Autodesk Fusion 360 part; units mm, degrees
(part 2 of 2)
sketch "Sketch8" plane through (0, 0, 0) normal (-1, 0, 0) x (0, -1, 0)
  circle A0 centre (117.475, 1.5875) radius 2.1
  line L0 (65.405, -4.7625) -> (65.405, -1.5875)
  line L1 (65.405, -1.5875) -> (133.35, -1.5875)
  line L2 (133.35, -1.5875) -> (133.35, 4.7625)
  line L3 (133.35, 4.7625) -> (-31.75, 4.7625)
  line L4 (-31.75, 4.7625) -> (-31.75, -4.7625)
  line L5 (-31.75, -4.7625) -> (65.405, -4.7625)
  circle A1 centre (117.475, 11.4427) radius 2.1
  circle A2 centre (117.475, 11.4427) radius 3.175
  circle A3 centre (106.045, 11.4427) radius 2.1
  circle A4 centre (106.045, 11.4427) radius 3.175
  line L6 (117.475, 8.2677) -> (106.045, 8.2677)
  line L7 (117.475, 14.6177) -> (106.045, 14.6177)
  line L8 (106.045, 14.6177) -> (70.9402, 14.6177)
  line L9 (70.9402, 14.6177) -> (65.405, 6.5046)
  line L10 (106.045, 8.2677) -> (74.295, 8.2677)
  line L11 (74.295, 8.2677) -> (65.405, -4.7625)
  line L12 (65.405, 6.5046) -> (65.405, -4.7625)
  line L13 (65.405, 6.5046) -> (64.2164, 4.7625)
  line L14 (120.65, 8.2677) -> (102.87, 8.2677)
  line L15 (102.87, 8.2677) -> (102.87, 14.6177)
  line L16 (102.87, 14.6177) -> (120.65, 14.6177)
  line L17 (120.65, 14.6177) -> (120.65, 8.2677)
  dimension "d38" = 4.2
  dimension "d39" = 9.8552
  dimension "d40" = 6.35
  dimension "d45" = 4.2
  dimension "d46" = 6.35
  dimension "d47" = 11.43
  dimension "d66" = 6.35
  dimension "d68" = 31.75
  dimension "d69" = 6.35
  constraint vertical A0.centre A1.centre
  constraint concentric A1 A2
  constraint concentric A3 A4
  constraint horizontal A1.centre A3.centre
  constraint coincident A2 L6.start
  constraint coincident A4 L6.end
  constraint coincident A2 L7.start
  constraint coincident A4 L7.end
  constraint tangent A4 L7
  constraint horizontal L6
  constraint horizontal L7
  constraint parallel L7 L8
  constraint parallel L3 L10
  constraint coincident L0.start L5.end
  constraint parallel L9 L11
  constraint vertical L9.end L0.start
  constraint coincident L3 L13.end
  constraint parallel L9 L13
  constraint horizontal L14
  constraint vertical L15
  constraint horizontal L16
  constraint vertical L17
  constraint coincident L8 L15.end
  constraint coincident L10 L14.end
  constraint tangent A2 L17
  constraint tangent A4 L15
  measures "d38" diameter of A1
  measures "d39" vertical distance of A0.centre A1.centre
  measures "d40" diameter of A2
  measures "d45" diameter of A3
  measures "d46" diameter of A4
  measures "d47" distance of A1.centre A3.centre
  measures "d66" distance of L8 L10
  measures "d68" distance of L6.end L10.end
  measures "d69" distance of L9 L11
extrude "Extrude7" cut sketch "Sketch8" against normal blind 6.35 contours L0 L1 L11 L12 | L1 L2 L3 L11
extrude "Extrude8" add sketch "Sketch8" along normal blind -6.35 and the other way blind 2.54 contours L0 L1 L11 L12 | L1 L3 L11 L12 | L3 L8 L9 L10 L11 L12 L15 | L3 L12 L13 | A4 L10 L14 L15 | A4 L8 L15 L16 | A4 | A2 A4 L6 L7 L14 L16 | A2 | A2 L14 L17 | A2 L16 L17 | A1 | A3
extrude "Extrude9" add sketch "Sketch8" against normal blind 2.54 contours L0 L1 L11 L12 | A4 L10 L14 L15 | A4 L8 L15 L16 | A4 | A2 A4 L6 L7 L14 L16 | A2 | A2 L14 L17 | A2 L16 L17 | A1 | A3
sketch "Sketch10" plane through (0, 0, -4.7625) normal (0, 0, -1) x (1, 0, 0)
  line L0 (6.35, 65.405) -> (0, 65.405)
  line L1 (0, 65.405) -> (0, -31.75)
  line L2 (0, -31.75) -> (6.35, -31.75)
  line L3 (6.35, -31.75) -> (6.35, 65.405)
  line L4 (6.35, -31.75) -> (0, -31.75)
  line L5 (0, -31.75) -> (0, 65.405)
  line L6 (0, 65.405) -> (6.35, 65.405)
  line L7 (6.35, 65.405) -> (6.35, -31.75)
  constraint horizontal L4
  constraint vertical L5
  constraint horizontal L6
  constraint vertical L7
  constraint coincident L0.end L1.start
  constraint coincident L2.end L3.start
extrude "Extrude12" add sketch "Sketch10" along normal blind 0.4318
sketch "Sketch9" plane through (6.35, 0, 0) normal (1, 0, 0) x (0, 1, 0)
  circle A0 centre (25.4, 0) radius 2.1971
  circle A1 centre (0, 0) radius 2.1971
  circle A2 centre (-12.7, 1.5875) radius 1.6
  circle A3 centre (-63.5, 1.5875) radius 1.6
  line L0 (-90.805, 4.7625) -> (-90.805, -4.7625)
  line L1 (-90.805, -4.7625) -> (31.75, -4.7625)
  line L2 (31.75, -4.7625) -> (31.75, 4.7625)
  line L3 (31.75, 4.7625) -> (-90.805, 4.7625)
  line L4 (17.4625, -1.5875) -> (17.4625, -4.7625)
  line L5 (17.4625, -4.7625) -> (7.9375, -4.7625)
  line L6 (7.9375, -4.7625) -> (7.9375, -1.5875)
  line L7 (7.9375, -1.5875) -> (17.4625, -1.5875)
  line L8 (0, -2.1971) -> (7.9375, -2.1971)
  dimension "d55" = 9.525
  dimension "d56" = 3.175
  dimension "d57" = 7.9375
  constraint vertical L4
  constraint horizontal L5
  constraint vertical L6
  constraint perpendicular L4 L7
  constraint collinear L1 L5
  constraint coincident A1 L8.start
  constraint coincident L6 L8.end
  constraint tangent A1 L8
  constraint perpendicular L6 L8
  measures "d55" distance of L6.end L4.start
  measures "d56" distance of L4.end L4.start
  measures "d57" distance of L8.start L8.end
extrude "Extrude10" [suppressed]
extrude "Extrude11" [suppressed]
equation "d7 = 0.5 in - ( 0.2 / 2 ) * 1 in"
equation "d10 = ( 0.375 / 2 ) * 1 in"
equation "d11 = ( ( 1.5 - 1 ) / 2 ) * 1 in"
equation "d39 = 0.263 in + 0.125 in"

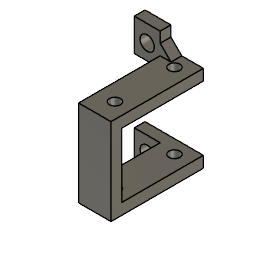
design "Yellow Motor Mount"
Autodesk Fusion 360 part; units mm, degrees
sketch "Sketch1" plane through (0, 0, 0) normal (0, 0, 1) x (1, 0, 0)
  line L0 (0, 0) -> (9.525, 0)
  line L1 (9.525, 0) -> (9.525, 27.1272)
  line L2 (9.525, 27.1272) -> (0, 27.1272)
  line L3 (0, 27.1272) -> (0, 0)
  circle A0 centre (5.0144, 5.675) radius 1.6
  circle A1 centre (5.0144, 23.1329) radius 1.6
  dimension "d1" = 3.2
  dimension "d2" = 3.2
  dimension "d3" = 17.4579
  dimension "d4" = 5.0144
  dimension "d5" = 5.675
  dimension "d6" = 9.525
  dimension "d7" = 27.1272
  constraint horizontal L0
  constraint vertical L1
  constraint horizontal L2
  constraint vertical L3
  constraint coincident L0.start L3.end
  constraint vertical A0.centre A1.centre
  measures "d1" diameter of A1
  measures "d2" diameter of A0
  measures "d3" distance of A0.centre A1.centre
  measures "d4" distance of L3 A1.centre
  measures "d5" distance of L0 A0.centre
  measures "d6" distance of L1 L3
  measures "d7" distance of L0 L2
extrude "Extrude1" add sketch "Sketch1" along normal blind 25.4
sketch "Sketch2" plane through (0, 0, 0) normal (-1, 0, 0) x (0, -1, 0)
  line L0 (-27.1272, 0) -> (0, 0)
  line L1 (0, 0) -> (0, 25.4)
  line L2 (0, 25.4) -> (-27.1272, 25.4)
  line L3 (-27.1272, 25.4) -> (-27.1272, 0)
  line L4 (-3.175, 3.302) -> (-27.1272, 3.302)
  line L5 (-27.1272, 3.302) -> (-27.1272, 22.1488)
  line L6 (-27.1272, 22.1488) -> (-3.175, 22.1488)
  line L7 (-3.175, 22.1488) -> (-3.175, 3.302)
  line L8 (-24.5872, 25.4) -> (-27.1272, 25.4)
  line L9 (-27.1272, 25.4) -> (-27.1272, 34.925)
  line L10 (-27.1272, 34.925) -> (-24.5872, 34.925)
  line L11 (-24.5872, 34.925) -> (-24.5872, 25.4)
  line L12 (-27.1272, 0) -> (-24.5872, 0)
  line L13 (-24.5872, 0) -> (-24.5872, -9.525)
  line L14 (-24.5872, -9.525) -> (-27.1272, -9.525)
  line L15 (-27.1272, -9.525) -> (-27.1272, 0)
  dimension "d11" = 3.302
  dimension "d12" = 18.8468
  dimension "d16" = 3.175
  dimension "d17" = 2.54
  dimension "d18" = 2.54
  dimension "d19" = 9.525
  dimension "d20" = 9.525
  constraint horizontal L4
  constraint vertical L5
  constraint horizontal L6
  constraint vertical L7
  constraint coincident L3 L5.end
  constraint horizontal L8
  constraint vertical L9
  constraint horizontal L10
  constraint vertical L11
  constraint coincident L2 L8.start
  constraint horizontal L12
  constraint vertical L13
  constraint horizontal L14
  constraint vertical L15
  constraint coincident L0.start L3.end
  constraint coincident L2.end L3.start
  measures "d11" distance of L0 L4
  measures "d12" distance of L4 L6
  measures "d16" distance of L1 L7
  measures "d17" distance of L9 L11
  measures "d18" distance of L13 L15
  measures "d19" distance of L8.start L10.end
  measures "d20" distance of L12.end L13.end
extrude "Extrude2" cut sketch "Sketch2" against normal blind 9.525 contours L3 L4 L5 L6 L7
sketch "Sketch3" plane through (0, 0, 0) normal (-1, 0, 0) x (0, -1, 0)
  line L0 (-3.175, 22.1488) -> (-3.175, 3.302)
  line L1 (-3.175, 3.302) -> (-27.1272, 3.302)
  line L2 (-27.1272, 3.302) -> (-27.1272, 0)
  line L3 (-27.1272, 0) -> (0, 0)
  line L4 (0, 0) -> (0, 25.4)
  line L5 (-27.1272, 3.302) -> (-23.9522, 3.302)
  line L6 (-23.9522, 3.302) -> (-23.9522, -6.223)
  line L7 (-23.9522, -6.223) -> (-27.1272, -6.223)
  line L8 (-27.1272, -6.223) -> (-27.1272, 3.302)
  line L9 (-27.1272, 22.1488) -> (-23.9522, 22.1488)
  line L10 (-23.9522, 22.1488) -> (-23.9522, 31.6738)
  line L11 (-23.9522, 31.6738) -> (-27.1272, 31.6738)
  line L12 (-27.1272, 31.6738) -> (-27.1272, 22.1488)
  point P0 (-27.1272, 22.1488)
  dimension "d23" = 3.175
  dimension "d24" = 9.525
  dimension "d26" = 9.525
  dimension "d27" = 3.175
  constraint horizontal L5
  constraint vertical L6
  constraint horizontal L7
  constraint vertical L8
  constraint coincident L1.end L2.start
  constraint horizontal L9
  constraint vertical L10
  constraint horizontal L11
  constraint vertical L12
  constraint coincident P0 L9.start
  measures "d23" distance of L6.end L7.end
  measures "d24" distance of L1.end L7.end
  measures "d26" distance of P0 L11.end
  measures "d27" distance of P0 L9.end
extrude "Extrude4" add sketch "Sketch3" along normal blind 7.62
chamfer "Chamfer1" distance 3.175 angle 45 2 edges at (0, 25.5397, 25.4) (0, 25.5397, 0)
sketch "Sketch4" plane through (0, 27.1272, 0) normal (0, 1, 0) x (-1, 0, 0)
  line L0 (-9.525, 22.1488) -> (7.62, 22.1488)
  line L1 (7.62, 22.1488) -> (7.62, 31.6738)
  line L2 (7.62, 31.6738) -> (0, 31.6738)
  line L3 (0, 31.6738) -> (0, 28.575)
  line L4 (0, 28.575) -> (-3.175, 25.4)
  line L5 (-3.175, 25.4) -> (-9.525, 25.4)
  line L6 (-9.525, 25.4) -> (-9.525, 22.1488)
  circle A0 centre (3.81, 26.7254) radius 2.1
  circle A1 centre (3.81, -1.2746) radius 2.1
  line L7 (3.81, 26.7254) -> (3.81, 31.6738)
  line L8 (3.81, -1.2746) -> (3.81, -6.223)
  line L9 (0, -6.223) -> (7.62, -6.223)
  dimension "d31" = 4.2
  dimension "d32" = 4.2
  dimension "d33" = 28
  dimension "d34" = 3.81
  constraint vertical A0.centre A1.centre
  constraint coincident A0.centre L7.start
  constraint midpoint L2 L7.end
  constraint coincident A1.centre L8.start
  constraint vertical L8
  constraint equal L7 L8
  constraint coincident L8.end L9
  measures "d31" diameter of A1
  measures "d32" diameter of A0
  measures "d33" distance of A0.centre A1.centre
  measures "d34" distance of L1 A0.centre
extrude "Extrude5" cut sketch "Sketch4" against normal blind 3.175 contours A0 | A1
equation "d5 = 2.5 mm + 0.125 in"
equation "d6 = ( 3 / 8 ) * 1 in"
equation "d7 = 0.943 in + 0.125 in"
equation "d11 = ( 1 - 0.74 ) / 2 * 1 in"
equation "d19 = ( 3 / 8 ) * 1 in"
equation "d20 = ( 3 / 8 ) * 1 in"
equation "d24 = ( 3 / 8 ) * 1 in"
equation "d26 = ( 3 / 8 ) * 1 in"

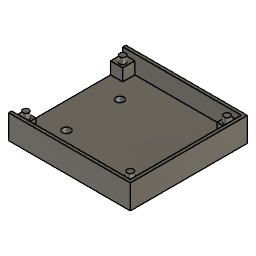
design "Controller Mounting"
Autodesk Fusion 360 part; units mm, degrees
sketch "Sketch1" plane through (0, 0, 0) normal (0, 0, 1) x (1, 0, 0)
  line L0 (0, 0) -> (65.175, 0)
  line L1 (65.175, 0) -> (65.175, 61.175)
  line L2 (65.175, 61.175) -> (0, 61.175)
  line L3 (0, 61.175) -> (0, 0)
  dimension "d1" = 61.175
  dimension "d2" = 65.175
  constraint horizontal L0
  constraint vertical L1
  constraint horizontal L2
  constraint vertical L3
  constraint coincident L0.start L3.end
  measures "d1" distance of L0.start L2.end
  measures "d2" distance of L0.start L0.end
extrude "Extrude1" add sketch "Sketch1" along normal blind 12.7
sketch "Sketch4" plane through (0, 0, 12.7) normal (0, 0, 1) x (-1, 0, 0)
  line L0 (0, -61.175) -> (0, 0)
  line L1 (0, 0) -> (-65.175, 0)
  line L2 (-65.175, 0) -> (-65.175, -61.175)
  line L3 (-65.175, -61.175) -> (0, -61.175)
  line L4 (-1.5875, -1.5875) -> (-63.5875, -1.5875)
  line L5 (-63.5875, -1.5875) -> (-63.5875, -59.5875)
  line L6 (-63.5875, -59.5875) -> (-1.5875, -59.5875)
  line L7 (-1.5875, -59.5875) -> (-1.5875, -1.5875)
  dimension "d10" = 1.5875
  dimension "d11" = 1.5875
  dimension "d12" = 1.5875
  dimension "d13" = 1.5875
  constraint horizontal L4
  constraint vertical L5
  constraint horizontal L6
  constraint vertical L7
  measures "d10" distance of L0 L7
  measures "d11" distance of L3 L6
  measures "d12" distance of L1 L4
  measures "d13" distance of L2 L5
extrude "Extrude2" cut sketch "Sketch4" against normal blind 9.525 contours L4 L5 L6 L7
sketch "Sketch5" plane through (0, 0, 0) normal (-1, 0, 0) x (0, -1, 0)
  line L0 (-61.175, 0) -> (0, 0)
  line L1 (0, 0) -> (0, 12.7)
  line L2 (0, 12.7) -> (-61.175, 12.7)
  line L3 (-61.175, 12.7) -> (-61.175, 0)
  line L4 (-53.2375, 12.7) -> (-7.9375, 12.7)
  line L5 (-7.9375, 12.7) -> (-7.9375, 0)
  line L6 (-53.2375, 0) -> (-53.2375, 12.7)
  line L7 (-53.2375, 3.175) -> (-59.5875, 3.175)
  line L8 (-59.5875, 3.175) -> (-59.5875, 12.7)
  line L9 (-59.5875, 12.7) -> (-53.2375, 12.7)
  line L10 (-53.2375, 12.7) -> (-53.2375, 3.175)
  line L11 (-7.9375, 3.175) -> (-1.5875, 3.175)
  line L12 (-1.5875, 3.175) -> (-1.5875, 12.7)
  line L13 (-1.5875, 12.7) -> (-7.9375, 12.7)
  line L14 (-7.9375, 12.7) -> (-7.9375, 3.175)
  line L15 (-53.2375, 3.175) -> (-7.9375, 3.175)
  dimension "d76" = 1.5875
  dimension "d77" = 3.175
  dimension "d78" = 3.175
  dimension "d79" = 1.5875
  dimension "d80" = 6.35
  dimension "d81" = 6.35
  constraint horizontal L4
  constraint vertical L5
  constraint vertical L6
  constraint coincident L2 L4.start
  constraint horizontal L5.end L6.start
  constraint horizontal L0.end L6.start
  constraint horizontal L7
  constraint vertical L8
  constraint horizontal L9
  constraint vertical L10
  constraint coincident L2 L8.end
  constraint coincident L6 L7.start
  constraint horizontal L11
  constraint vertical L12
  constraint horizontal L13
  constraint vertical L14
  constraint coincident L2 L12.end
  constraint coincident L5 L11.start
  measures "d76" distance of L3 L8
  measures "d77" distance of L0 L7
  measures "d78" distance of L0 L11
  measures "d79" distance of L1 L12
  measures "d80" distance of L8 L10
  measures "d81" distance of L12 L14
extrude "Extrude3" cut sketch "Sketch5" against normal blind 1.5875
sketch "Sketch6" plane through (0, 0, 3.175) normal (0, 0, 1) x (-1, 0, 0)
  circle A0 centre (-59.8375, -5.3375) radius 1.65
  circle A1 centre (-5.3375, -5.3375) radius 1.65
  circle A2 centre (-59.8375, -55.8375) radius 1.65
  circle A3 centre (-5.3375, -55.8375) radius 1.65
  line L0 (-63.5875, -1.5875) -> (-57.2375, -1.5875)
  line L1 (-57.2375, -1.5875) -> (-57.2375, -7.9375)
  line L2 (-57.2375, -7.9375) -> (-63.5875, -7.9375)
  line L3 (-63.5875, -7.9375) -> (-63.5875, -1.5875)
  line L4 (-63.5875, -59.5875) -> (-57.2375, -59.5875)
  line L5 (-57.2375, -59.5875) -> (-57.2375, -53.2375)
  line L6 (-57.2375, -53.2375) -> (-63.5875, -53.2375)
  line L7 (-63.5875, -53.2375) -> (-63.5875, -59.5875)
  line L8 (-1.5875, -59.5875) -> (-7.9375, -59.5875)
  line L9 (-7.9375, -59.5875) -> (-7.9375, -53.2375)
  line L10 (-7.9375, -53.2375) -> (-1.5875, -53.2375)
  line L11 (-1.5875, -53.2375) -> (-1.5875, -59.5875)
  line L12 (-1.5875, -1.5875) -> (-7.9375, -1.5875)
  line L13 (-7.9375, -1.5875) -> (-7.9375, -7.9375)
  line L14 (-7.9375, -7.9375) -> (-1.5875, -7.9375)
  line L15 (-1.5875, -7.9375) -> (-1.5875, -1.5875)
  line L16 (-65.175, 0) -> (-65.175, -61.175)
  line L17 (-65.175, -61.175) -> (0, -61.175)
  line L18 (-1.5875, -1.5875) -> (-63.5875, -1.5875)
  line L19 (-63.5875, -1.5875) -> (-63.5875, -59.5875)
  line L20 (-63.5875, -59.5875) -> (-1.5875, -59.5875)
  line L21 (-1.5875, -59.5875) -> (-1.5875, -1.5875)
  dimension "d82" = 3.3
  dimension "d83" = 50.5
  dimension "d84" = 50.5
  dimension "d85" = 54.5
  dimension "d86" = 3.3
  dimension "d87" = 3.3
  dimension "d88" = 5.3375
  dimension "d89" = 5.3375
  dimension "d90" = 6.35
  dimension "d91" = 6.35
  dimension "d92" = 6.35
  dimension "d93" = 6.35
  dimension "d94" = 6.35
  dimension "d95" = 6.35
  dimension "d96" = 6.35
  dimension "d97" = 6.35
  dimension "d98" = 1.5875
  dimension "d100" = 1.5875
  dimension "d101" = 1.5875
  dimension "d102" = 1.5875
  constraint horizontal A0.centre A1.centre
  constraint horizontal A2.centre A3.centre
  constraint vertical A1.centre A3.centre
  constraint equal A0 A1
  constraint horizontal L0
  constraint vertical L1
  constraint horizontal L2
  constraint vertical L3
  constraint horizontal L4
  constraint vertical L5
  constraint horizontal L6
  constraint vertical L7
  constraint horizontal L8
  constraint vertical L9
  constraint horizontal L10
  constraint vertical L11
  constraint horizontal L12
  constraint vertical L13
  constraint horizontal L14
  constraint vertical L15
  constraint horizontal L1.end L13.end
  constraint vertical L9.end L13.end
  constraint horizontal L5.end L9.end
  constraint vertical L1.end L5.end
  measures "d82" diameter of A0
  measures "d83" distance of A0.centre A2.centre
  measures "d84" vertical distance of A1.centre A3.centre
  measures "d85" distance of A0.centre A1.centre
  measures "d86" diameter of A2
  measures "d87" diameter of A3
  measures "d88" vertical distance of origin A0.centre
  measures "d89" horizontal distance of origin A1.centre
  measures "d90" distance of L12.end L13.end
  measures "d91" distance of L13.end L14.end
  measures "d92" distance of L9.end L10.end
  measures "d93" distance of L8.end L9.end
  measures "d94" distance of L4.end L5.end
  measures "d95" distance of L5.end L6.end
  measures "d96" distance of L1.end L2.end
  measures "d97" distance of L0.end L1.end
  measures "d98" distance of origin L12
  measures "d100" distance of origin L15
  measures "d101" distance of L3 L16
  measures "d102" distance of L4 L17
extrude "Extrude4" add sketch "Sketch6" along normal blind 6.35 contours A0 | A1 | A2 | A3 | L0 L1 L2 L3 L18 L19 | L12 L13 L14 L15 L18 L21 | L4 L5 L6 L7 L19 L20 | L8 L9 L10 L11 L20 L21
extrude "Extrude8" add sketch "Sketch6" along normal blind 9.525 contours A0 | A1 | A2 | A3
sketch "Sketch7" plane through (0, 0, 3.175) normal (0, 0, 1) x (-1, 0, 0)
  line L0 (-7.9375, -1.5875) -> (-57.2375, -1.5875)
  circle A0 centre (-15.2005, -16.6175) radius 2.1
  circle A1 centre (-15.2005, -44.5575) radius 2.1
  line L1 (-1.5875, 0) -> (-65.175, 0)
  line L2 (-15.2005, -16.6175) -> (-15.2005, -44.5575)
  line L3 (-15.2005, 0) -> (-15.2005, -61.175)
  line L4 (-65.175, -61.175) -> (-1.5875, -61.175)
  line L5 (-57.2375, -59.5875) -> (-7.9375, -59.5875)
  line L6 (-63.5875, -7.9375) -> (-63.5875, -53.2375)
  line L7 (-63.5875, -53.2375) -> (-57.2375, -53.2375)
  line L8 (-57.2375, -53.2375) -> (-57.2375, -59.5875)
  line L9 (-7.9375, -59.5875) -> (-7.9375, -53.2375)
  line L10 (-7.9375, -53.2375) -> (-1.5875, -53.2375)
  line L11 (-1.5875, -53.2375) -> (-1.5875, -7.9375)
  line L12 (-1.5875, -7.9375) -> (-7.9375, -7.9375)
  line L13 (-7.9375, -7.9375) -> (-7.9375, -1.5875)
  line L14 (-57.2375, -1.5875) -> (-57.2375, -7.9375)
  line L15 (-57.2375, -7.9375) -> (-63.5875, -7.9375)
  dimension "d41" = 4.2
  dimension "d42" = 4.2
  dimension "d43" = 27.94
  dimension "d108" = 13.613
  constraint vertical A0.centre A1.centre
  constraint coincident A0.centre L2.start
  constraint coincident A1.centre L2.end
  constraint coincident L1 L3.start
  constraint midpoint L2 L3
  constraint coincident L3.end L4
  constraint vertical L3.start L3.end
  measures "d41" diameter of A1
  measures "d42" diameter of A0
  measures "d43" distance of A0.centre A1.centre
  measures "d108" distance of L2 L11
extrude "Extrude5" cut sketch "Sketch7" against normal blind 3.175 contours A0 L2 L3 | A0 L2 L3 | A1 L2 L3 | A1 L2 L3
sketch "Sketch9" plane through (0, 0, 0) normal (0, 0, -1) x (1, 0, 0)
  line L0 (1.5875, -61.175) -> (65.175, -61.175)
  line L1 (65.175, -61.175) -> (65.175, 0)
  line L2 (65.175, 0) -> (1.5875, 0)
  circle A0 centre (19.0373, -54.4) radius 1.6
  circle A1 centre (44.4373, -54.4) radius 1.6
  circle A2 centre (19.0373, -6.775) radius 1.6
  circle A3 centre (44.4373, -6.775) radius 1.6
  circle A4 centre (15.2005, -16.6175) radius 2.1
  circle A5 centre (15.2005, -44.5575) radius 2.1
  line L3 (44.4373, -6.775) -> (44.4373, 0)
  line L4 (44.4373, -54.4) -> (44.4373, -61.175)
  line L5 (1.5875, 0) -> (1.5875, -61.175)
  dimension "d60" = 3.2
  dimension "d61" = 3.2
  dimension "d75" = 25.4
  dimension "d105" = 47.625
  dimension "d106" = 47.625
  constraint vertical A0.centre A2.centre
  constraint vertical A1.centre A3.centre
  constraint equal A0 A2
  constraint equal A0 A3
  constraint horizontal A2.centre A3.centre
  constraint coincident A3.centre L3.start
  constraint coincident L2 L3.end
  constraint perpendicular L2 L3
  constraint coincident A1.centre L4.start
  constraint coincident L0 L4.end
  constraint perpendicular L0 L4
  constraint equal L3 L4
  measures "d60" diameter of A0
  measures "d61" diameter of A1
  measures "d75" distance of A0.centre A1.centre
  measures "d105" distance of A1.centre A3.centre
  measures "d106" distance of A0.centre A2.centre
equation "d1 = 58 mm + 0.125 in"
equation "d2 = 62 mm + 0.125 in"
equation "d10 = ( 1 / 16 ) * 1 in"
equation "d11 = ( 1 / 16 ) * 1 in"
equation "d12 = ( 1 / 16 ) * 1 in"
equation "d13 = ( 1 / 16 ) * 1 in"
equation "d14 = -0.5 in + 0.125 in"
equation "d20 = ( -1 / 16 ) * 1 in"
equation "d76 = ( 1 / 16 ) * 1 in"
equation "d79 = ( 1 / 16 ) * 1 in"
equation "d88 = ( 1 / 16 ) * 1 in + 3.75 mm"
equation "d89 = ( 1 / 16 ) * 1 in + 3.75 mm"
equation "d98 = ( 1 / 16 ) * 1 in"
equation "d100 = ( 1 / 16 ) * 1 in"
equation "d101 = ( 1 / 16 ) * 1 in"
equation "d102 = ( 1 / 16 ) * 1 in"
equation "d57 = 1.8 in + 0.388 in"
equation "d58 = 0.5 in - 0.052 in - 0.0865 in + 0.388 in"
equation "d71 = 0.101 in + ( 0.173 / 2 ) * 1 in"
equation "d72 = 0.101 in + ( 0.173 / 2 ) * 1 in"

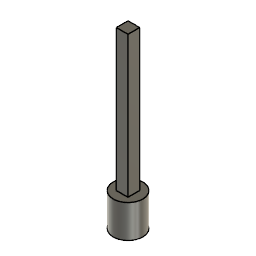
design "Yellow Motor Wheel"
Autodesk Fusion 360 part; units mm, degrees
sketch "Sketch1" plane through (0, 0, 0) normal (0, 0, 1) x (1, 0, 0)
  circle A0 centre (0, 0) radius 2.72
  line L0 (-1.85, 1.994) -> (-1.85, -1.994)
  line L1 (1.85, 1.994) -> (1.85, -1.994)
  circle A1 centre (0, 0) radius 3.99
  dimension "d1" = 5.44
  dimension "d3" = 3.7
  dimension "d4" = 1.27
  constraint coincident A0.centre A1.centre
  constraint vertical L0
  constraint vertical L1
  constraint coincident A0 L0.start
  constraint coincident A0 L1.start
  constraint coincident A0 L1.end
  constraint coincident A0 L0.end
  constraint equal L0 L1
  measures "d1" diameter of A0
  measures "d3" distance of L0 L1
  measures "d4" distance of A0 A1
extrude "Extrude1" add sketch "Sketch1" along normal blind 6.35 contours A0 L1 | A0 L0 | A1
sketch "Sketch2" plane through (0, 0, 6.35) normal (0, 0, 1) x (-1, 0, 0)
  line L0 (1.85, 1.994) -> (1.85, -1.994)
  arc A0 (-1.85, -1.994) -> (1.85, -1.994) centre (0, 0) ccw
  line L1 (-1.85, -1.994) -> (-1.85, 1.994)
  arc A1 (1.85, 1.994) -> (-1.85, 1.994) centre (0, 0) ccw
  circle A2 centre (0, 0) radius 3.99
  circle A3 centre (0, 0) radius 3.99
  dimension "d7" = 7.98
  constraint concentric A0 A3
  measures "d7" diameter of A3
extrude "Extrude2" add sketch "Sketch2" along normal blind 2.54 contours L0 A0 L1 A1 | A2 A3
sketch "Sketch3" plane through (0, 0, 8.89) normal (0, 0, 1) x (-1, 0, 0)
  circle A0 centre (0, 0) radius 3.99
  line L0 (1.5875, 1.5875) -> (-1.5875, 1.5875)
  line L1 (-1.5875, 1.5875) -> (-1.5875, -1.5875)
  line L2 (-1.5875, -1.5875) -> (1.5875, -1.5875)
  line L3 (1.5875, -1.5875) -> (1.5875, 1.5875)
  line L4 (1.5875, 1.5875) -> (-1.5875, -1.5875) construction
  line L5 (-1.5875, 1.5875) -> (1.5875, -1.5875) construction
  dimension "d10" = 3.175
  dimension "d11" = 3.175
  constraint horizontal L0
  constraint perpendicular L0 L1
  constraint parallel L0 L2
  constraint parallel L1 L3
  constraint coincident L4 A0.centre
  constraint coincident L5 A0.centre
  constraint coincident A0.centre origin
  measures "d10" distance of L0.start L2.end
  measures "d11" distance of L1.end L2.end
extrude "Extrude3" add sketch "Sketch3" along normal blind 38.1 contours L0 L1 L2 L3

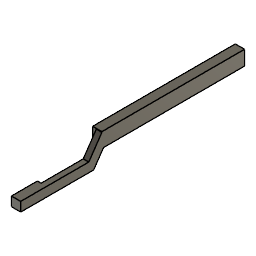
design "Right Cross Beam"
Autodesk Fusion 360 part; units mm, degrees
sketch "Sketch1" plane through (0, 0, 0) normal (1, 0, 0) x (0, 1, 0)
  circle A0 centre (0, 0) radius 2.1971
  circle A1 centre (25.4, 0) radius 2.1971
  line L0 (10.16, 2.54) -> (15.24, 2.54)
  line L1 (15.24, 2.54) -> (15.24, -2.54)
  line L2 (15.24, -2.54) -> (10.16, -2.54)
  line L3 (10.16, -2.54) -> (10.16, 2.54)
  line L4 (-6.35, 4.7625) -> (31.75, 4.7625)
  line L5 (31.75, 4.7625) -> (31.75, -4.7625)
  line L6 (31.75, -4.7625) -> (-6.35, -4.7625)
  line L7 (-6.35, -4.7625) -> (-6.35, 4.7625)
  dimension "d1" = 25.4
  dimension "d2" = 4.3942
  dimension "d3" = 4.3942
  dimension "d4" = 5.08
  dimension "d5" = 5.08
  dimension "d6" = 2.54
  dimension "d7" = 10.16
  dimension "d8" = 9.525
  dimension "d9" = 38.1
  dimension "d10" = 4.7625
  dimension "d11" = 6.35
  constraint horizontal A0.centre A1.centre
  constraint horizontal L0
  constraint vertical L1
  constraint horizontal L2
  constraint vertical L3
  constraint coincident A0.centre origin
  constraint horizontal L4
  constraint vertical L5
  constraint horizontal L6
  constraint vertical L7
  measures "d1" distance of A0.centre A1.centre
  measures "d2" diameter of A0
  measures "d3" diameter of A1
  measures "d4" distance of L0.start L0.end
  measures "d5" distance of L0.start L2.end
  measures "d6" distance of A0.centre L0
  measures "d7" horizontal distance of A0.centre L2.end
  measures "d8" distance of L4.start L6.end
  measures "d9" distance of L4.start L4.end
  measures "d10" distance of A0.centre L4
  measures "d11" distance of A0.centre L7
extrude "Extrude1" add sketch "Sketch1" along normal blind 2.54 contours A0 | A1 | L0 L1 L2 L3 | L4 L5 L6 L7 makes body 1
sketch "Sketch2" plane through (2.54, 0, 0) normal (1, 0, 0) x (0, 1, 0)
  line L0 (-6.35, -4.7625) -> (31.75, -4.7625)
  line L1 (31.75, -4.7625) -> (31.75, 4.7625)
  line L2 (31.75, 4.7625) -> (-6.35, 4.7625)
  line L3 (-6.35, 4.7625) -> (-6.35, -4.7625)
  line L4 (31.75, 4.7625) -> (-6.35, 4.7625)
  line L5 (-6.35, 4.7625) -> (-6.35, -4.7625)
  line L6 (-6.35, -4.7625) -> (31.75, -4.7625)
  line L7 (31.75, -4.7625) -> (31.75, 4.7625)
  circle A0 centre (0, 0) radius 2.1971
  circle A1 centre (25.4, 0) radius 2.1971
  dimension "d14" = 4.3942
  dimension "d15" = 4.3942
  constraint horizontal L4
  constraint vertical L5
  constraint horizontal L6
  constraint vertical L7
  constraint coincident L0.start L3.end
  constraint coincident L1.end L2.start
  measures "d14" diameter of A0
  measures "d15" diameter of A1
extrude "Extrude2" add sketch "Sketch2" along normal blind 3.81 contours L0 L1 L2 L3 L4 L5 L6 L7 | A0 | A1 bodies 1
sketch "Sketch3" plane through (0, -6.35, 0) normal (0, -1, 0) x (1, 0, 0)
  line L0 (0, 4.7625) -> (0, -4.7625)
  line L1 (0, -4.7625) -> (6.35, -4.7625)
  line L2 (6.35, -4.7625) -> (6.35, 4.7625)
  line L3 (6.35, 4.7625) -> (0, 4.7625)
  line L4 (0, 4.7625) -> (6.35, 4.7625)
  line L5 (6.35, 4.7625) -> (6.35, -4.7625)
  line L6 (6.35, -4.7625) -> (0, -4.7625)
  line L7 (0, -4.7625) -> (0, 4.7625)
  constraint horizontal L4
  constraint vertical L5
  constraint horizontal L6
  constraint vertical L7
  constraint coincident L1.end L2.start
  constraint coincident L0.start L3.end
extrude "Extrude3" add sketch "Sketch3" along normal blind 127 bodies 1
sketch "Sketch4" plane through (6.35, 0, 0) normal (1, 0, 0) x (0, 1, 0)
  line L0 (31.75, -4.7625) -> (31.75, 4.7625)
  line L1 (31.75, 4.7625) -> (-133.35, 4.7625)
  line L2 (-133.35, 4.7625) -> (-133.35, -4.7625)
  line L3 (-133.35, -4.7625) -> (31.75, -4.7625)
  circle A0 centre (-22.225, -1.5875) radius 1.6
  circle A1 centre (-47.625, -1.5875) radius 1.6
  dimension "d20" = 3.2
  dimension "d21" = 3.2
  dimension "d24" = 6.35
  dimension "d25" = 22.225
  dimension "d48" = 25.4
  constraint horizontal A0.centre A1.centre
  measures "d20" diameter of A0
  measures "d21" diameter of A1
  measures "d24" distance of L1 A0.centre
  measures "d25" horizontal distance of origin A0.centre
  measures "d48" distance of A0.centre A1.centre
sketch "Sketch5" plane through (0, -133.35, 0) normal (0, -1, 0) x (1, 0, 0)
  line L0 (0, -4.7625) -> (6.35, -4.7625)
  line L1 (6.35, -4.7625) -> (6.35, 4.7625)
  line L2 (6.35, 4.7625) -> (0, 4.7625)
  line L3 (0, 4.7625) -> (0, -4.7625)
  line L4 (0, -4.7625) -> (6.35, -4.7625)
  line L5 (6.35, -4.7625) -> (6.35, 1.5875)
  line L6 (6.35, 1.5875) -> (0, 1.5875)
  line L7 (0, 1.5875) -> (0, -4.7625)
  dimension "d29" = 6.35
  constraint horizontal L4
  constraint vertical L5
  constraint horizontal L6
  constraint vertical L7
  constraint coincident L1 L5.end
  constraint coincident L0.start L3.end
  measures "d29" distance of L0.end L5.end
extrude "Extrude5" cut sketch "Sketch5" against normal blind 67.945 contours L1 L2 L3 L6 bodies 1
sketch "Sketch6" plane through (0, 0, 0) normal (-1, 0, 0) x (0, -1, 0)
  line L0 (65.405, 1.5875) -> (65.405, 4.7625)
  line L1 (65.405, 4.7625) -> (-31.75, 4.7625)
  line L2 (-31.75, 4.7625) -> (-31.75, -4.7625)
  line L3 (-31.75, -4.7625) -> (133.35, -4.7625)
  line L4 (133.35, -4.7625) -> (133.35, 1.5875)
  line L5 (133.35, 1.5875) -> (65.405, 1.5875)
  circle A0 centre (117.475, -1.5875) radius 2.1
  dimension "d32" = 4.2
  dimension "d33" = 15.875
  dimension "d34" = 3.175
  measures "d32" diameter of A0
  measures "d33" distance of L4 A0.centre
  measures "d34" distance of L3 A0.centre
extrude "Extrude6" cut sketch "Sketch6" against normal blind 6.35 contours A0 bodies 1
sketch "Sketch7" plane through (6.35, 0, 0) normal (1, 0, 0) x (0, 1, 0)
  circle A0 centre (-117.475, -1.5875) radius 2.1
  line L0 (-65.405, 4.7625) -> (-65.405, 1.5875)
  line L1 (-65.405, 1.5875) -> (-133.35, 1.5875)
  line L2 (-133.35, 1.5875) -> (-133.35, -4.7625)
  line L3 (-133.35, -4.7625) -> (31.75, -4.7625)
  line L4 (31.75, -4.7625) -> (31.75, 4.7625)
  line L5 (31.75, 4.7625) -> (-65.405, 4.7625)
  circle A1 centre (-117.475, -11.4427) radius 2.1
  circle A2 centre (-117.475, -11.4427) radius 3.175
  circle A3 centre (-106.045, -11.4427) radius 2.1
  circle A4 centre (-106.045, -11.4427) radius 3.175
  line L6 (-117.475, -8.2677) -> (-106.045, -8.2677)
  line L7 (-117.475, -14.6177) -> (-106.045, -14.6177)
  line L8 (-65.405, 4.7625) -> (-65.405, -4.7625)
  line L9 (-106.045, -14.6177) -> (-70.9402, -14.6177)
  line L10 (-70.9402, -14.6177) -> (-65.405, -6.5046)
  line L11 (-106.045, -8.2677) -> (-74.295, -8.2677)
  line L12 (-74.295, -8.2677) -> (-65.405, 4.7625)
  line L13 (-65.405, -6.5046) -> (-65.405, -4.7625)
  line L14 (-65.405, -6.5046) -> (-64.2164, -4.7625)
  line L15 (-120.65, -8.2677) -> (-102.87, -8.2677)
  line L16 (-102.87, -8.2677) -> (-102.87, -14.6177)
  line L17 (-102.87, -14.6177) -> (-120.65, -14.6177)
  line L18 (-120.65, -14.6177) -> (-120.65, -8.2677)
  dimension "d37" = 9.8552
  dimension "d38" = 6.35
  dimension "d43" = 4.2
  dimension "d44" = 6.35
  dimension "d45" = 11.43
  dimension "d49" = 31.75
  dimension "d50" = 6.35
  constraint equal A0 A1
  constraint vertical A0.centre A1.centre
  constraint concentric A1 A2
  constraint concentric A3 A4
  constraint horizontal A1.centre A3.centre
  constraint coincident A2 L6.start
  constraint coincident A4 L6.end
  constraint parallel L3 L6
  constraint coincident A2 L7.start
  constraint coincident A4 L7.end
  constraint coincident L3 L8.end
  constraint horizontal L7
  constraint tangent A2 L7
  constraint tangent A2 L6
  constraint vertical L8.end L0.start
  constraint tangent A4 L9
  constraint parallel L3 L9
  constraint coincident L8 L10.end
  constraint tangent A4 L11
  constraint parallel L3 L11
  constraint coincident L0.start L5.end
  constraint vertical L0.start L5.end
  constraint parallel L10 L12
  constraint coincident L3 L14.end
  constraint parallel L10 L14
  constraint horizontal L15
  constraint vertical L16
  constraint horizontal L17
  constraint vertical L18
  constraint coincident L9 L16.end
  constraint tangent A4 L16
  constraint tangent A2 L18
  constraint coincident L11 L15.end
  measures "d37" vertical distance of A0.centre A1.centre
  measures "d38" diameter of A2
  measures "d43" diameter of A3
  measures "d44" diameter of A4
  measures "d45" distance of A1.centre A3.centre
  measures "d49" horizontal distance of A3.centre L11.end
  measures "d50" distance of L10 L12
extrude "Extrude7" cut sketch "Sketch7" against normal blind 6.35 contours L0 L1 L8 L12 | L1 L3 L8 L12 | L1 L2 L3 L12 bodies 1
extrude "Extrude8" add sketch "Sketch7" against normal blind 3.81 separate body contours L0 L1 L8 L12 | L1 L3 L8 L12 | L3 L9 L10 L11 L12 L13 L16 | L3 L13 L14 | A4 L11 L15 L16 | A4 L9 L16 L17 | A4 | A2 A4 L6 L7 L15 L17 | A2 | A2 L15 L18 | A2 L17 L18 | A1 | A3 makes body 2
extrude "Extrude9" add sketch "Sketch7" against normal blind 6.35 contours A4 L11 L15 L16 | A4 L9 L16 L17 | A4 | A2 A4 L6 L7 L15 L17 | A2 | A2 L15 L18 | A2 L17 L18 | A1 | A3 bodies 2
sketch "Sketch8" plane through (0, 0, 4.7625) normal (0, 0, 1) x (-1, 0, 0)
  line L0 (0, 65.405) -> (-6.35, 65.405)
  line L1 (-6.35, 65.405) -> (-6.35, -31.75)
  line L2 (-6.35, -31.75) -> (0, -31.75)
  line L3 (0, -31.75) -> (0, 65.405)
  line L4 (0, -31.75) -> (-6.35, -31.75)
  line L5 (-6.35, -31.75) -> (-6.35, 65.405)
  line L6 (-6.35, 65.405) -> (0, 65.405)
  line L7 (0, 65.405) -> (0, -31.75)
  constraint horizontal L4
  constraint vertical L5
  constraint horizontal L6
  constraint vertical L7
  constraint coincident L0.end L1.start
  constraint coincident L2.end L3.start
extrude "Extrude10" add sketch "Sketch8" along normal blind 0.4318 bodies 1 2
equation "d7 = 0.5 in - ( 0.2 / 2 ) * 1 in"
equation "d10 = ( 0.375 / 2 ) * 1 in"
equation "d11 = ( ( 1.5 - 1 ) / 2 ) * 1 in"
equation "d37 = 0.263 in + 0.125 in"
